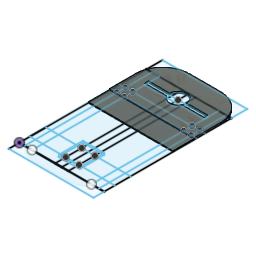
PIANOBACKChassisRaffaello (Autodesk Fusion 360 design; units mm, degrees)
part number: 2025-06-29-10-43-15-579
Autodesk Fusion 360 part; units mm, degrees
sketch "Schizzo1" plane through (0, 0, 0) normal (0, 0, 1) x (1, 0, 0)
  line L0 (0, 0) -> (160, 0)
  line L1 (160, 0) -> (160, 240)
  line L2 (160, 240) -> (0, 240)
  line L3 (0, 240) -> (0, 0)
  line L4 (0, 0) -> (80, 0)
  line L5 (80, 0) -> (80, 240)
  line L6 (0, 240) -> (10, 240)
  line L7 (0, 240) -> (10, 240)
  line L8 (10, 240) -> (10, 0)
  line L9 (160, 240) -> (150, 240)
  line L10 (150, 0) -> (150, 240)
  line L11 (0, 190) -> (160, 190)
  line L12 (10, 190) -> (10, 174)
  line L13 (10, 174) -> (160, 174)
  line L14 (10, 174) -> (0, 174)
  line L15 (10, 240) -> (24, 240)
  line L16 (24, 240) -> (24, 0)
  line L17 (150, 240) -> (136, 240)
  line L18 (136, 240) -> (136, 0)
  line L19 (80, 0) -> (67.5, 0)
  line L20 (67.5, 0) -> (67.5, 240)
  line L21 (80, 0) -> (92.5, 0)
  line L22 (92.5, 0) -> (92.5, 240)
  line L23 (0, 20) -> (160, 20)
  line L24 (0, 20) -> (0, 50)
  line L25 (0, 50) -> (160, 50)
  circle A0 centre (10, 190) radius 2
  circle A1 centre (10, 174) radius 2
  circle A2 centre (24, 190) radius 2
  circle A3 centre (24, 174) radius 2
  circle A4 centre (136, 190) radius 2
  circle A5 centre (150, 190) radius 2
  circle A6 centre (136, 174) radius 2
  circle A7 centre (150, 174) radius 2
  circle A8 centre (67.5, 20) radius 2
  circle A9 centre (67.5, 50) radius 2
  circle A10 centre (92.5, 50) radius 2
  circle A11 centre (92.5, 20) radius 2
  line L26 (60, 60) -> (100, 60)
  line L27 (100, 60) -> (100, 14)
  line L28 (100, 14) -> (60, 14)
  line L29 (60, 14) -> (60, 60)
  line L30 (24, 219.5723) -> (136, 219.5723)
  line L31 (136, 219.5723) -> (136, 212.5723)
  line L32 (136, 212.5723) -> (24, 212.5723)
  line L33 (24, 212.5723) -> (24, 219.5723)
  circle A12 centre (80, 219.5723) radius 16.0281
  line L34 (0, 240) -> (160, 240)
  line L35 (160, 240) -> (160, 270)
  line L36 (160, 270) -> (0, 270)
  line L37 (0, 270) -> (0, 240)
  line L38 (0, 0) -> (160, 0)
  line L39 (160, 0) -> (160, -20)
  line L40 (160, -20) -> (0, -20)
  line L41 (0, -20) -> (0, 0)
  dimension "d1" = 160
  dimension "d2" = 240
  dimension "d3" = 80
  dimension "d4" = 16
  dimension "d5" = 14
  dimension "d6" = 240
  dimension "d7" = 14
  dimension "d8" = 240
  dimension "d9" = 12.5
  dimension "d10" = 12.5
  dimension "d11" = 30
  dimension "d12" = 4
  dimension "d13" = 4
  dimension "d14" = 4
  dimension "d15" = 4
  dimension "d16" = 4
  dimension "d17" = 4
  dimension "d18" = 4
  dimension "d19" = 4
  dimension "d20" = 4
  dimension "d21" = 4
  dimension "d22" = 4
  dimension "d23" = 4
  dimension "d24" = 40
  dimension "d25" = 46
  dimension "d26" = 7
  constraint horizontal L0
  constraint vertical L1
  constraint horizontal L2
  constraint vertical L3
  constraint coincident L0.start L3.end
  constraint perpendicular L3 L4
  constraint midpoint L2 L5.end
  constraint coincident L2 L6.end
  constraint coincident L4 L8.end
  constraint coincident L2 L9.end
  constraint coincident L0 L10.start
  constraint perpendicular L9 L10
  constraint coincident L3 L11.start
  constraint coincident L1 L11.end
  constraint perpendicular L1 L11
  constraint coincident L8 L12.start
  constraint coincident L11 L12.start
  constraint perpendicular L11 L12
  constraint coincident L1 L13.end
  constraint perpendicular L1 L13
  constraint coincident L3 L14.end
  constraint perpendicular L3 L14
  constraint perpendicular L8 L15
  constraint vertical L16
  constraint perpendicular L10 L17
  constraint vertical L18
  constraint perpendicular L5 L19
  constraint coincident L2 L20.end
  constraint perpendicular L2 L20
  constraint perpendicular L5 L21
  constraint coincident L2 L22.end
  constraint perpendicular L2 L22
  constraint coincident L3 L23.start
  constraint coincident L1 L23.end
  constraint perpendicular L1 L23
  constraint perpendicular L23 L24
  constraint coincident L1 L25.end
  constraint perpendicular L1 L25
  constraint coincident L12.start A0.centre
  constraint coincident L12.end L13.start
  constraint coincident L16 A2.centre
  constraint coincident L11 A2.centre
  constraint coincident L13 A3.centre
  constraint coincident L16 A3.centre
  constraint coincident L11 A4.centre
  constraint coincident L18 A4.centre
  constraint coincident L10 A5.centre
  constraint coincident L11 A5.centre
  constraint coincident L18 A6.centre
  constraint coincident L13 A6.centre
  constraint coincident L13 A7.centre
  constraint coincident L10 A7.centre
  constraint coincident L23 A8.centre
  constraint coincident L20 A8.centre
  constraint coincident L25 A9.centre
  constraint coincident L20 A9.centre
  constraint coincident L25 A10.centre
  constraint coincident L22 A10.centre
  constraint coincident L22 A11.centre
  constraint coincident L23 A11.centre
  constraint horizontal L26
  constraint vertical L27
  constraint horizontal L28
  constraint vertical L29
  constraint horizontal L30
  constraint vertical L31
  constraint horizontal L32
  constraint vertical L33
  constraint coincident L18 L31.end
  constraint coincident L16 L30.start
  constraint midpoint L30 A12.centre
  constraint horizontal L34
  constraint vertical L35
  constraint horizontal L36
  constraint vertical L37
  constraint horizontal L38
  constraint vertical L39
  constraint horizontal L40
  constraint vertical L41
  measures "d1" distance of L0.start L0.end
  measures "d2" distance of L0.start L2.end
  measures "d3" distance of L0.start L4.end
  measures "d4" distance of L12.start L12.end
  measures "d5" distance of L6.end L15.end
  measures "d6" distance of L15.end L16.end
  measures "d7" distance of L9.end L17.end
  measures "d8" distance of L17.end L18.end
  measures "d9" distance of L4.end L19.end
  measures "d10" distance of L4.end L21.end
  measures "d11" distance of L23.start L24.end
  measures "d12" diameter of A0
  measures "d13" diameter of A1
  measures "d14" diameter of A2
  measures "d15" diameter of A3
  measures "d16" diameter of A4
  measures "d17" diameter of A5
  measures "d18" diameter of A6
  measures "d19" diameter of A7
  measures "d20" diameter of A8
  measures "d21" diameter of A9
  measures "d22" diameter of A10
  measures "d23" diameter of A11
  measures "d24" distance of L26.start L26.end
  measures "d25" distance of L26.start L28.end
  measures "d26" distance of L30.start L32.end
extrude "Estrusione1" add sketch "Schizzo1" along normal blind 3 contours L0 L3 L4 L8 L23 L38 | L0 L4 L19 L21 L38 L39 L40 L41 | L0 L4 L8 L16 L23 L38 | L3 L8 L23 L24 L25 | L0 L4 L16 L20 L23 L28 L29 L38 | L8 L16 L23 L25 | L3 L8 L14 L25 A1 | L0 L4 L5 L19 L20 L28 L38 | L16 L23 L25 L29 | L8 L13 L16 L25 A1 A3 | L3 L8 L11 L12 L14 A0 A1 | L0 L1 L10 L23 L38 | L0 L5 L21 L22 L28 L38 | L20 L23 A8 L28 L29 | L5 L20 L23 A8 L28 | L13 L16 L20 L25 A3 L26 L29 | L20 L23 L25 A8 A9 L29 | L2 L3 L6 L7 L8 L11 A0 L34 | L0 L10 L18 L23 L38 | L1 L10 L23 L25 | L0 L18 L22 L23 L27 L28 L38 | L5 L22 L23 A11 L28 | L20 L25 A9 L26 L29 | L8 L11 L12 L13 L16 A0 A1 A2 A3 | L2 L6 L7 L9 L15 L17 L34 L35 L36 L37 | L10 L18 L23 L25 | L1 L10 L13 L25 A7 | L22 L23 A11 L27 L28 | L5 L20 L23 L25 A8 A9 | L5 L22 L23 L25 A10 A11 | L11 L13 L16 L20 A2 A3 | L2 L8 L11 L15 L16 A0 A2 L33 L34 | L18 L23 L25 L27 | L10 L13 L18 L25 A6 A7 | L1 L10 L11 L13 A5 A7 | L5 L20 L25 A9 L26 | L5 L22 L25 A10 L26 | L5 L11 L13 L20 | L5 L13 L20 L26 | L2 L16 L20 L30 A12 L34 | L13 L18 L22 L25 A6 L26 L27 | L22 L23 L25 A10 A11 L27 | L1 L2 L9 L10 L11 A5 L34 | L5 L13 L22 L26 | L5 L11 L13 L22 | L5 L11 L20 A12 | L11 L16 L20 A2 L32 A12 | L2 L5 L20 A12 L34 | L22 L25 A10 L26 L27 | L10 L11 L13 L18 A4 A5 A6 A7 | L5 L11 L22 A12 | L11 L13 L18 L22 A4 A6 | L2 L5 L22 A12 L34 | L2 L10 L11 L17 L18 A4 A5 L31 L34 | L11 L18 L22 A4 L32 A12 | L2 L18 L22 L30 A12 L34
fillet "Raccordo1" radius 50 2 edges at (160, -20, 1.5) (0, -20, 1.5)
fillet "Raccordo2" radius 50 2 edges at (0, 270, 1.5) (160, 270, 1.5)
sketch "Schizzo2" plane through (0, 0, 3) normal (0, 0, 1) x (-1, 0, 0)
  circle A0 centre (-10, -174) radius 2
  circle A1 centre (-136, -190) radius 2
  circle A2 centre (-67.5, -20) radius 2
  circle A3 centre (-10, -190) radius 2
  circle A4 centre (-92.5, -50) radius 2
  circle A5 centre (-136, -174) radius 2
  circle A6 centre (-24, -190) radius 2
  circle A7 centre (-150, -174) radius 2
  circle A8 centre (-67.5, -50) radius 2
  circle A9 centre (-24, -174) radius 2
  circle A10 centre (-150, -190) radius 2
  line L0 (-96.0281, -219.5723) -> (-136, -219.5723)
  line L1 (-136, -219.5723) -> (-136, -212.5723)
  line L2 (-136, -212.5723) -> (-94.4187, -212.5723)
  arc A11 (-65.5813, -212.5723) -> (-94.4187, -212.5723) centre (-80, -219.5723) ccw
  line L3 (-65.5813, -212.5723) -> (-24, -212.5723)
  line L4 (-24, -212.5723) -> (-24, -219.5723)
  line L5 (-24, -219.5723) -> (-63.9719, -219.5723)
  arc A12 (-96.0281, -219.5723) -> (-63.9719, -219.5723) centre (-80, -219.5723) ccw
  circle A13 centre (-92.5, -20) radius 2
  arc A14 (-160, -220) -> (-110, -270) centre (-110, -220) ccw
  line L6 (-110, -270) -> (-50, -270)
  arc A15 (-50, -270) -> (0, -220) centre (-50, -220) ccw
  line L7 (0, -220) -> (0, -30)
  arc A16 (0, -30) -> (-50, 20) centre (-50, -30) ccw
  line L8 (-50, 20) -> (-110, 20)
  arc A17 (-110, 20) -> (-160, -30) centre (-110, -30) ccw
  line L9 (-160, -30) -> (-160, -220)
  line L10 (-60, -60) -> (-100, -60)
  line L11 (-100, -60) -> (-100, -15)
  line L12 (-100, -15) -> (-60, -15)
  line L13 (-60, -15) -> (-60, -60)
  constraint horizontal L10
  constraint vertical L11
  constraint horizontal L12
  constraint vertical L13
sketch "Schizzo4" plane through (0, 0, 3) normal (0, 0, 1) x (-1, 0, 0)
  circle A0 centre (-10, -174) radius 2
  circle A1 centre (-136, -190) radius 2
  circle A2 centre (-67.5, -20) radius 2
  circle A3 centre (-10, -190) radius 2
  circle A4 centre (-92.5, -50) radius 2
  circle A5 centre (-136, -174) radius 2
  circle A6 centre (-24, -190) radius 2
  circle A7 centre (-150, -174) radius 2
  circle A8 centre (-67.5, -50) radius 2
  circle A9 centre (-24, -174) radius 2
  circle A10 centre (-150, -190) radius 2
  line L0 (-96.0281, -219.5723) -> (-136, -219.5723)
  line L1 (-136, -219.5723) -> (-136, -212.5723)
  line L2 (-136, -212.5723) -> (-94.4187, -212.5723)
  arc A11 (-65.5813, -212.5723) -> (-94.4187, -212.5723) centre (-80, -219.5723) ccw
  line L3 (-65.5813, -212.5723) -> (-24, -212.5723)
  line L4 (-24, -212.5723) -> (-24, -219.5723)
  line L5 (-24, -219.5723) -> (-63.9719, -219.5723)
  arc A12 (-96.0281, -219.5723) -> (-63.9719, -219.5723) centre (-80, -219.5723) ccw
  circle A13 centre (-92.5, -20) radius 2
  arc A14 (-160, -220) -> (-110, -270) centre (-110, -220) ccw
  line L6 (-110, -270) -> (-50, -270)
  arc A15 (-50, -270) -> (0, -220) centre (-50, -220) ccw
  line L7 (0, -220) -> (0, -30)
  arc A16 (0, -30) -> (-50, 20) centre (-50, -30) ccw
  line L8 (-50, 20) -> (-110, 20)
  arc A17 (-110, 20) -> (-160, -30) centre (-110, -30) ccw
  line L9 (-160, -30) -> (-160, -220)
  line L10 (0, -130) -> (-180, -130)
  line L11 (-180, -130) -> (-180, -280)
  line L12 (-180, -280) -> (0, -280)
  line L13 (0, -280) -> (0, -130)
  constraint horizontal L10
  constraint vertical L11
  constraint horizontal L12
  constraint vertical L13
  constraint coincident L7 L10.start
extrude "Estrusione4" cut sketch "Schizzo4" against normal blind 50 contours L7 A16 L8 A17 L9 L10
sketch "Schizzo5" plane through (0, 0, 3) normal (0, 0, 1) x (-1, 0, 0)
  line L0 (0, -130) -> (-168.0031, -130)
  line L1 (-168.0031, -130) -> (-168.0031, -170)
  line L2 (-168.0031, -170) -> (0, -170)
  line L3 (0, -170) -> (0, -130)
  dimension "d41" = 40
  constraint horizontal L0
  constraint vertical L1
  constraint horizontal L2
  constraint vertical L3
  measures "d41" distance of L0.start L2.end
extrude "Estrusione5" cut sketch "Schizzo5" against normal blind 1.5
extrude "Estrusione3" [rolled back] along distance -60 taper angle 0
extrude "Estrusione2" [rolled back] along distance 12 taper angle 0
fillet "Raccordo3" [rolled back] radius 5
sketch "Schizzo3" plane through (0, 0, 0) normal (0, 0, 1) x (1, 0, 0)
